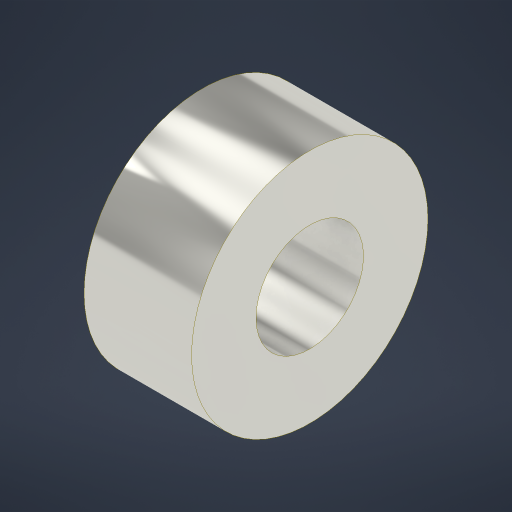
# Autodesk Inventor part: 685ZZ_(618[slash]5)
Saved by Autodesk Inventor 2023 (Build 270158000, 158)
## iProperties
Created: 2026-11-12
Part Number: 685ZZ_(618[slash]5)
Material: Steel
Document SubType Name: Modeling
Designer: szykr
Density: 7.85 g/cm^3
Appearance: Silver
Author: szykr
Autodesk Inventor part; units mm, degrees
ref_plane "YZ Plane" through (0, 0, 0) normal (1, 0, 0) x (0, 1, 0)
ref_plane "XZ Plane" through (0, 0, 0) normal (0, 1, 0) x (-1, 0, 0)
ref_plane "XY Plane" through (0, 0, 0) normal (0, 0, 1) x (1, 0, 0)
sketch "Sketch1" plane through (0, 0, 0) normal (0, 1, 0) x (-1, 0, 0)
  line L0 (0, 0) -> (29.2917, 0) construction
  line L1 (0, 2.5) -> (5, 2.5)
  line L2 (5, 2.5) -> (5, 5.5)
  line L3 (5, 5.5) -> (0, 5.5)
  line L4 (0, 5.5) -> (0, 2.5)
  dimension "d0" = 5
  dimension "d1" = 5
  dimension "d2" = 11
  constraints: 10 end point, 3 perpendicular, 2 horizontal, 1 vertical alignment
  measures "d0" diameter of L1 L0
  measures "d1" distance between parallel lines of L2 L4
  measures "d2" diameter of L3 L0
revolve "Revolution1" add sketch "Sketch1" angle 360 about axis through (0, 0, 0) along (-1, 0, 0)
body "Solid1"
